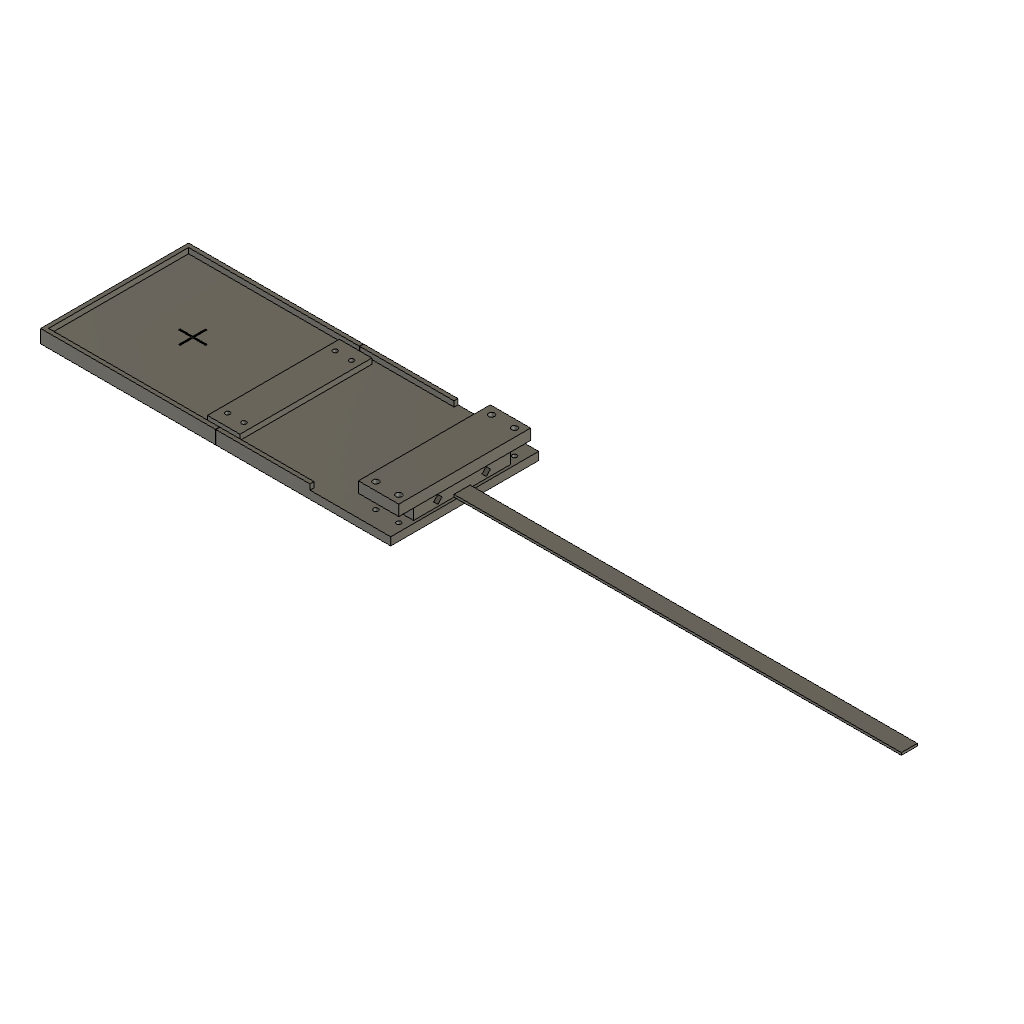
SkySafe_Weighted_Holder (Autodesk Fusion 360 design; units mm, degrees)
part number: 2026-10-11-03-14-07-749
part number: 2026-10-11-03-14-08-487
part number: 2026-10-11-03-14-09-230
part number: 2026-10-11-03-14-09-832
part number: 2026-10-11-03-14-10-188
part number: 2026-10-11-03-14-11-813
Autodesk Fusion 360 part; units mm, degrees
sketch "Flat root support floor sketch" plane through (0, 0, 0) normal (0, 0, 1) x (1, 0, 0) in component "01 Weighted root base - PRINT ONE"
  line L0 (-104, -55) -> (26, -55)
  line L1 (26, -55) -> (26, 55)
  line L2 (26, 55) -> (-104, 55)
  line L3 (-104, 55) -> (-104, -55)
extrude "Flat root support floor" add sketch "Flat root support floor sketch" along normal blind 6 makes body 1 in component "01 Weighted root base - PRINT ONE"
ref_plane "WorkPlane1" through (0, 0, 5.95) normal (0, 0, 1) x (1, 0, 0) in component "01 Weighted root base - PRINT ONE"
sketch "Front tray side lip -55 sketch" plane through (0, 0, 5.95) normal (0, 0, 1) x (1, 0, 0) in component "01 Weighted root base - PRINT ONE"
  line L0 (-104, -55) -> (-34, -55)
  line L1 (-34, -55) -> (-34, -52)
  line L2 (-34, -52) -> (-104, -52)
  line L3 (-104, -52) -> (-104, -55)
extrude "Front tray side lip -55" add sketch "Front tray side lip -55 sketch" along normal blind 4.05 bodies 1 in component "01 Weighted root base - PRINT ONE"
ref_plane "WorkPlane2" through (0, 0, 5.95) normal (0, 0, 1) x (1, 0, 0) in component "01 Weighted root base - PRINT ONE"
sketch "Front tray side lip 52 sketch" plane through (0, 0, 5.95) normal (0, 0, 1) x (1, 0, 0) in component "01 Weighted root base - PRINT ONE"
  line L0 (-104, 52) -> (-34, 52)
  line L1 (-34, 52) -> (-34, 55)
  line L2 (-34, 55) -> (-104, 55)
  line L3 (-104, 55) -> (-104, 52)
extrude "Front tray side lip 52" add sketch "Front tray side lip 52 sketch" along normal blind 4.05 bodies 1 in component "01 Weighted root base - PRINT ONE"
ref_plane "WorkPlane3" through (0, 0, 5.95) normal (0, 0, 1) x (1, 0, 0) in component "01 Weighted root base - PRINT ONE"
sketch "Original root locating pin -8" plane through (0, 0, 5.95) normal (0, 0, 1) x (1, 0, 0) in component "01 Weighted root base - PRINT ONE"
  circle A0 centre (8, -8) radius 1.5
extrude "Root locating pin -8" add sketch "Original root locating pin -8" along normal blind 2.05 bodies 1 in component "01 Weighted root base - PRINT ONE"
ref_plane "WorkPlane4" through (0, 0, 5.95) normal (0, 0, 1) x (1, 0, 0) in component "01 Weighted root base - PRINT ONE"
sketch "Original root locating pin 8" plane through (0, 0, 5.95) normal (0, 0, 1) x (1, 0, 0) in component "01 Weighted root base - PRINT ONE"
  circle A0 centre (8, 8) radius 1.5
extrude "Root locating pin 8" add sketch "Original root locating pin 8" along normal blind 2.05 bodies 1 in component "01 Weighted root base - PRINT ONE"
ref_plane "WorkPlane5" through (0, 0, -0.05) normal (0, 0, 1) x (1, 0, 0) in component "01 Weighted root base - PRINT ONE"
sketch "Root bolt (3, -43) clearance sketch" plane through (0, 0, -0.05) normal (0, 0, 1) x (1, 0, 0) in component "01 Weighted root base - PRINT ONE"
  circle A0 centre (3, -43) radius 1.7
  dimension "d25" = 3.4
  measures "d25" diameter of A0
extrude "Root bolt (3, -43) clearance" cut sketch "Root bolt (3, -43) clearance sketch" along normal blind 6.1 bodies 1 in component "01 Weighted root base - PRINT ONE"
ref_plane "WorkPlane6" through (0, 0, -0.05) normal (0, 0, 1) x (1, 0, 0) in component "01 Weighted root base - PRINT ONE"
sketch "Root bolt (3, -43) recessed head sketch" plane through (0, 0, -0.05) normal (0, 0, 1) x (1, 0, 0) in component "01 Weighted root base - PRINT ONE"
  circle A0 centre (3, -43) radius 3.2
  dimension "d30" = 6.4
  measures "d30" diameter of A0
extrude "Root bolt (3, -43) recessed head" cut sketch "Root bolt (3, -43) recessed head sketch" along normal blind 3.4 bodies 1 in component "01 Weighted root base - PRINT ONE"
ref_plane "WorkPlane7" through (0, 0, -0.05) normal (0, 0, 1) x (1, 0, 0) in component "01 Weighted root base - PRINT ONE"
sketch "Root bolt (3, 43) clearance sketch" plane through (0, 0, -0.05) normal (0, 0, 1) x (1, 0, 0) in component "01 Weighted root base - PRINT ONE"
  circle A0 centre (3, 43) radius 1.7
  dimension "d35" = 3.4
  measures "d35" diameter of A0
extrude "Root bolt (3, 43) clearance" cut sketch "Root bolt (3, 43) clearance sketch" along normal blind 6.1 bodies 1 in component "01 Weighted root base - PRINT ONE"
ref_plane "WorkPlane8" through (0, 0, -0.05) normal (0, 0, 1) x (1, 0, 0) in component "01 Weighted root base - PRINT ONE"
sketch "Root bolt (3, 43) recessed head sketch" plane through (0, 0, -0.05) normal (0, 0, 1) x (1, 0, 0) in component "01 Weighted root base - PRINT ONE"
  circle A0 centre (3, 43) radius 3.2
  dimension "d40" = 6.4
  measures "d40" diameter of A0
extrude "Root bolt (3, 43) recessed head" cut sketch "Root bolt (3, 43) recessed head sketch" along normal blind 3.4 bodies 1 in component "01 Weighted root base - PRINT ONE"
ref_plane "WorkPlane9" through (0, 0, -0.05) normal (0, 0, 1) x (1, 0, 0) in component "01 Weighted root base - PRINT ONE"
sketch "Root bolt (20, -43) clearance sketch" plane through (0, 0, -0.05) normal (0, 0, 1) x (1, 0, 0) in component "01 Weighted root base - PRINT ONE"
  circle A0 centre (20, -43) radius 1.7
  dimension "d45" = 3.4
  measures "d45" diameter of A0
extrude "Root bolt (20, -43) clearance" cut sketch "Root bolt (20, -43) clearance sketch" along normal blind 6.1 bodies 1 in component "01 Weighted root base - PRINT ONE"
ref_plane "WorkPlane10" through (0, 0, -0.05) normal (0, 0, 1) x (1, 0, 0) in component "01 Weighted root base - PRINT ONE"
sketch "Root bolt (20, -43) recessed head sketch" plane through (0, 0, -0.05) normal (0, 0, 1) x (1, 0, 0) in component "01 Weighted root base - PRINT ONE"
  circle A0 centre (20, -43) radius 3.2
  dimension "d50" = 6.4
  measures "d50" diameter of A0
extrude "Root bolt (20, -43) recessed head" cut sketch "Root bolt (20, -43) recessed head sketch" along normal blind 3.4 bodies 1 in component "01 Weighted root base - PRINT ONE"
ref_plane "WorkPlane11" through (0, 0, -0.05) normal (0, 0, 1) x (1, 0, 0) in component "01 Weighted root base - PRINT ONE"
sketch "Root bolt (20, 43) clearance sketch" plane through (0, 0, -0.05) normal (0, 0, 1) x (1, 0, 0) in component "01 Weighted root base - PRINT ONE"
  circle A0 centre (20, 43) radius 1.7
  dimension "d55" = 3.4
  measures "d55" diameter of A0
extrude "Root bolt (20, 43) clearance" cut sketch "Root bolt (20, 43) clearance sketch" along normal blind 6.1 bodies 1 in component "01 Weighted root base - PRINT ONE"
ref_plane "WorkPlane12" through (0, 0, -0.05) normal (0, 0, 1) x (1, 0, 0) in component "01 Weighted root base - PRINT ONE"
sketch "Root bolt (20, 43) recessed head sketch" plane through (0, 0, -0.05) normal (0, 0, 1) x (1, 0, 0) in component "01 Weighted root base - PRINT ONE"
  circle A0 centre (20, 43) radius 3.2
  dimension "d60" = 6.4
  measures "d60" diameter of A0
extrude "Root bolt (20, 43) recessed head" cut sketch "Root bolt (20, 43) recessed head sketch" along normal blind 3.4 bodies 1 in component "01 Weighted root base - PRINT ONE"
ref_plane "WorkPlane13" through (0, 0, -0.05) normal (0, 0, 1) x (1, 0, 0) in component "01 Weighted root base - PRINT ONE"
sketch "Tray joint front bolt -40 clearance sketch" plane through (0, 0, -0.05) normal (0, 0, 1) x (1, 0, 0) in component "01 Weighted root base - PRINT ONE"
  circle A0 centre (-98, -40) radius 1.7
  dimension "d65" = 3.4
  measures "d65" diameter of A0
extrude "Tray joint front bolt -40 clearance" cut sketch "Tray joint front bolt -40 clearance sketch" along normal blind 6.1 bodies 1 in component "01 Weighted root base - PRINT ONE"
ref_plane "WorkPlane14" through (0, 0, -0.05) normal (0, 0, 1) x (1, 0, 0) in component "01 Weighted root base - PRINT ONE"
sketch "Tray joint front bolt -40 recessed head sketch" plane through (0, 0, -0.05) normal (0, 0, 1) x (1, 0, 0) in component "01 Weighted root base - PRINT ONE"
  circle A0 centre (-98, -40) radius 3.2
  dimension "d70" = 6.4
  measures "d70" diameter of A0
extrude "Tray joint front bolt -40 recessed head" cut sketch "Tray joint front bolt -40 recessed head sketch" along normal blind 3.4 bodies 1 in component "01 Weighted root base - PRINT ONE"
ref_plane "WorkPlane15" through (0, 0, -0.05) normal (0, 0, 1) x (1, 0, 0) in component "01 Weighted root base - PRINT ONE"
sketch "Tray joint front bolt 40 clearance sketch" plane through (0, 0, -0.05) normal (0, 0, 1) x (1, 0, 0) in component "01 Weighted root base - PRINT ONE"
  circle A0 centre (-98, 40) radius 1.7
  dimension "d75" = 3.4
  measures "d75" diameter of A0
extrude "Tray joint front bolt 40 clearance" cut sketch "Tray joint front bolt 40 clearance sketch" along normal blind 6.1 bodies 1 in component "01 Weighted root base - PRINT ONE"
ref_plane "WorkPlane16" through (0, 0, -0.05) normal (0, 0, 1) x (1, 0, 0) in component "01 Weighted root base - PRINT ONE"
sketch "Tray joint front bolt 40 recessed head sketch" plane through (0, 0, -0.05) normal (0, 0, 1) x (1, 0, 0) in component "01 Weighted root base - PRINT ONE"
  circle A0 centre (-98, 40) radius 3.2
  dimension "d80" = 6.4
  measures "d80" diameter of A0
extrude "Tray joint front bolt 40 recessed head" cut sketch "Tray joint front bolt 40 recessed head sketch" along normal blind 3.4 bodies 1 in component "01 Weighted root base - PRINT ONE"
sketch "Rear tray floor sketch" plane through (0, 0, 0) normal (0, 0, 1) x (1, 0, 0) in component "02 Rear ballast tray - PRINT ONE"
  line L0 (-104, -55) -> (26, -55)
  line L1 (26, -55) -> (26, 55)
  line L2 (26, 55) -> (-104, 55)
  line L3 (-104, 55) -> (-104, -55)
extrude "Rear tray floor" add sketch "Rear tray floor sketch" along normal blind 6 separate body makes body 2 in component "02 Rear ballast tray - PRINT ONE"
ref_plane "WorkPlane1" through (0, 0, 5.95) normal (0, 0, 1) x (1, 0, 0) in component "02 Rear ballast tray - PRINT ONE"
sketch "Rear weight stop sketch" plane through (0, 0, 5.95) normal (0, 0, 1) x (1, 0, 0) in component "02 Rear ballast tray - PRINT ONE"
  line L0 (-104, -55) -> (-101, -55)
  line L1 (-101, -55) -> (-101, 55)
  line L2 (-101, 55) -> (-104, 55)
  line L3 (-104, 55) -> (-104, -55)
extrude "Rear weight stop" add sketch "Rear weight stop sketch" along normal blind 4.05 bodies 2 in component "02 Rear ballast tray - PRINT ONE"
ref_plane "WorkPlane2" through (0, 0, 5.95) normal (0, 0, 1) x (1, 0, 0) in component "02 Rear ballast tray - PRINT ONE"
sketch "Rear tray side lip -55 sketch" plane through (0, 0, 5.95) normal (0, 0, 1) x (1, 0, 0) in component "02 Rear ballast tray - PRINT ONE"
  line L0 (-104, -55) -> (26, -55)
  line L1 (26, -55) -> (26, -52)
  line L2 (26, -52) -> (-104, -52)
  line L3 (-104, -52) -> (-104, -55)
extrude "Rear tray side lip -55" add sketch "Rear tray side lip -55 sketch" along normal blind 4.05 bodies 2 in component "02 Rear ballast tray - PRINT ONE"
ref_plane "WorkPlane3" through (0, 0, 5.95) normal (0, 0, 1) x (1, 0, 0) in component "02 Rear ballast tray - PRINT ONE"
sketch "Rear tray side lip 52 sketch" plane through (0, 0, 5.95) normal (0, 0, 1) x (1, 0, 0) in component "02 Rear ballast tray - PRINT ONE"
  line L0 (-104, 52) -> (26, 52)
  line L1 (26, 52) -> (26, 55)
  line L2 (26, 55) -> (-104, 55)
  line L3 (-104, 55) -> (-104, 52)
extrude "Rear tray side lip 52" add sketch "Rear tray side lip 52 sketch" along normal blind 4.05 bodies 2 in component "02 Rear ballast tray - PRINT ONE"
ref_plane "WorkPlane4" through (0, 0, -0.05) normal (0, 0, 1) x (1, 0, 0) in component "02 Rear ballast tray - PRINT ONE"
sketch "Tray joint rear bolt -40 clearance sketch" plane through (0, 0, -0.05) normal (0, 0, 1) x (1, 0, 0) in component "02 Rear ballast tray - PRINT ONE"
  circle A0 centre (20, -40) radius 1.7
  dimension "d99" = 3.4
  measures "d99" diameter of A0
extrude "Tray joint rear bolt -40 clearance" cut sketch "Tray joint rear bolt -40 clearance sketch" along normal blind 6.1 bodies 2 in component "02 Rear ballast tray - PRINT ONE"
ref_plane "WorkPlane5" through (0, 0, -0.05) normal (0, 0, 1) x (1, 0, 0) in component "02 Rear ballast tray - PRINT ONE"
sketch "Tray joint rear bolt -40 recessed head sketch" plane through (0, 0, -0.05) normal (0, 0, 1) x (1, 0, 0) in component "02 Rear ballast tray - PRINT ONE"
  circle A0 centre (20, -40) radius 3.2
  dimension "d104" = 6.4
  measures "d104" diameter of A0
extrude "Tray joint rear bolt -40 recessed head" cut sketch "Tray joint rear bolt -40 recessed head sketch" along normal blind 3.4 bodies 2 in component "02 Rear ballast tray - PRINT ONE"
ref_plane "WorkPlane6" through (0, 0, -0.05) normal (0, 0, 1) x (1, 0, 0) in component "02 Rear ballast tray - PRINT ONE"
sketch "Tray joint rear bolt 40 clearance sketch" plane through (0, 0, -0.05) normal (0, 0, 1) x (1, 0, 0) in component "02 Rear ballast tray - PRINT ONE"
  circle A0 centre (20, 40) radius 1.7
  dimension "d109" = 3.4
  measures "d109" diameter of A0
extrude "Tray joint rear bolt 40 clearance" cut sketch "Tray joint rear bolt 40 clearance sketch" along normal blind 6.1 bodies 2 in component "02 Rear ballast tray - PRINT ONE"
ref_plane "WorkPlane7" through (0, 0, -0.05) normal (0, 0, 1) x (1, 0, 0) in component "02 Rear ballast tray - PRINT ONE"
sketch "Tray joint rear bolt 40 recessed head sketch" plane through (0, 0, -0.05) normal (0, 0, 1) x (1, 0, 0) in component "02 Rear ballast tray - PRINT ONE"
  circle A0 centre (20, 40) radius 3.2
  dimension "d114" = 6.4
  measures "d114" diameter of A0
extrude "Tray joint rear bolt 40 recessed head" cut sketch "Tray joint rear bolt 40 recessed head sketch" along normal blind 3.4 bodies 2 in component "02 Rear ballast tray - PRINT ONE"
ref_plane "WorkPlane8" through (0, 0, 5.6) normal (0, 0, 1) x (1, 0, 0) in component "02 Rear ballast tray - PRINT ONE"
sketch "Weight center line X sketch" plane through (0, 0, 5.6) normal (0, 0, 1) x (1, 0, 0) in component "02 Rear ballast tray - PRINT ONE"
  line L0 (-46.3, -10) -> (-45.3, -10)
  line L1 (-45.3, -10) -> (-45.3, 10)
  line L2 (-45.3, 10) -> (-46.3, 10)
  line L3 (-46.3, 10) -> (-46.3, -10)
extrude "Weight center line X" cut sketch "Weight center line X sketch" along normal blind 0.5 bodies 2 in component "02 Rear ballast tray - PRINT ONE"
ref_plane "WorkPlane9" through (0, 0, 5.6) normal (0, 0, 1) x (1, 0, 0) in component "02 Rear ballast tray - PRINT ONE"
sketch "Weight center line Y sketch" plane through (0, 0, 5.6) normal (0, 0, 1) x (1, 0, 0) in component "02 Rear ballast tray - PRINT ONE"
  line L0 (-55.8, -0.5) -> (-35.8, -0.5)
  line L1 (-35.8, -0.5) -> (-35.8, 0.5)
  line L2 (-35.8, 0.5) -> (-55.8, 0.5)
  line L3 (-55.8, 0.5) -> (-55.8, -0.5)
extrude "Weight center line Y" cut sketch "Weight center line Y sketch" along normal blind 0.5 bodies 2 in component "02 Rear ballast tray - PRINT ONE"
sketch "Wide upper splice sketch" plane through (0, 0, 0) normal (0, 0, 1) x (1, 0, 0) in component "03 Tray joint bridge - PRINT ONE"
  line L0 (0, -49) -> (24.2, -49)
  line L1 (24.2, -49) -> (24.2, 49)
  line L2 (24.2, 49) -> (0, 49)
  line L3 (0, 49) -> (0, -49)
extrude "Wide upper splice" add sketch "Wide upper splice sketch" along normal blind 4 separate body makes body 3 in component "03 Tray joint bridge - PRINT ONE"
ref_plane "WorkPlane1" through (0, 0, -0.05) normal (0, 0, 1) x (1, 0, 0) in component "03 Tray joint bridge - PRINT ONE"
sketch "Tray splice hole (6, -40) sketch" plane through (0, 0, -0.05) normal (0, 0, 1) x (1, 0, 0) in component "03 Tray joint bridge - PRINT ONE"
  circle A0 centre (6, -40) radius 1.7
  dimension "d129" = 3.4
  measures "d129" diameter of A0
extrude "Tray splice hole (6, -40)" cut sketch "Tray splice hole (6, -40) sketch" along normal blind 4.1 bodies 3 in component "03 Tray joint bridge - PRINT ONE"
ref_plane "WorkPlane2" through (0, 0, -0.05) normal (0, 0, 1) x (1, 0, 0) in component "03 Tray joint bridge - PRINT ONE"
sketch "Tray splice hole (6, 40) sketch" plane through (0, 0, -0.05) normal (0, 0, 1) x (1, 0, 0) in component "03 Tray joint bridge - PRINT ONE"
  circle A0 centre (6, 40) radius 1.7
  dimension "d134" = 3.4
  measures "d134" diameter of A0
extrude "Tray splice hole (6, 40)" cut sketch "Tray splice hole (6, 40) sketch" along normal blind 4.1 bodies 3 in component "03 Tray joint bridge - PRINT ONE"
ref_plane "WorkPlane3" through (0, 0, -0.05) normal (0, 0, 1) x (1, 0, 0) in component "03 Tray joint bridge - PRINT ONE"
sketch "Tray splice hole (18.2, -40) sketch" plane through (0, 0, -0.05) normal (0, 0, 1) x (1, 0, 0) in component "03 Tray joint bridge - PRINT ONE"
  circle A0 centre (18.2, -40) radius 1.7
  dimension "d139" = 3.4
  measures "d139" diameter of A0
extrude "Tray splice hole (18.2, -40)" cut sketch "Tray splice hole (18.2, -40) sketch" along normal blind 4.1 bodies 3 in component "03 Tray joint bridge - PRINT ONE"
ref_plane "WorkPlane4" through (0, 0, -0.05) normal (0, 0, 1) x (1, 0, 0) in component "03 Tray joint bridge - PRINT ONE"
sketch "Tray splice hole (18.2, 40) sketch" plane through (0, 0, -0.05) normal (0, 0, 1) x (1, 0, 0) in component "03 Tray joint bridge - PRINT ONE"
  circle A0 centre (18.2, 40) radius 1.7
  dimension "d144" = 3.4
  measures "d144" diameter of A0
extrude "Tray splice hole (18.2, 40)" cut sketch "Tray splice hole (18.2, 40) sketch" along normal blind 4.1 bodies 3 in component "03 Tray joint bridge - PRINT ONE"
sketch "Original upper root jaw sketch" plane through (0, 0, 0) normal (0, 0, 1) x (1, 0, 0) in component "04 Existing root cap - REUSE"
  line L0 (-4, -49) -> (26, -49)
  line L1 (26, -49) -> (26, 49)
  line L2 (26, 49) -> (-4, 49)
  line L3 (-4, 49) -> (-4, -49)
extrude "Original upper root jaw" add sketch "Original upper root jaw sketch" along normal blind 8 separate body makes body 4 in component "04 Existing root cap - REUSE"
ref_plane "WorkPlane1" through (0, 0, -0.05) normal (0, 0, 1) x (1, 0, 0) in component "04 Existing root cap - REUSE"
sketch "Original M4 clearance (3, -43) sketch" plane through (0, 0, -0.05) normal (0, 0, 1) x (1, 0, 0) in component "04 Existing root cap - REUSE"
  circle A0 centre (3, -43) radius 2.2
extrude "Original M4 clearance (3, -43)" cut sketch "Original M4 clearance (3, -43) sketch" along normal blind 8.1 bodies 4 in component "04 Existing root cap - REUSE"
ref_plane "WorkPlane2" through (0, 0, -0.05) normal (0, 0, 1) x (1, 0, 0) in component "04 Existing root cap - REUSE"
sketch "Original M4 clearance (3, 43) sketch" plane through (0, 0, -0.05) normal (0, 0, 1) x (1, 0, 0) in component "04 Existing root cap - REUSE"
  circle A0 centre (3, 43) radius 2.2
extrude "Original M4 clearance (3, 43)" cut sketch "Original M4 clearance (3, 43) sketch" along normal blind 8.1 bodies 4 in component "04 Existing root cap - REUSE"
ref_plane "WorkPlane3" through (0, 0, -0.05) normal (0, 0, 1) x (1, 0, 0) in component "04 Existing root cap - REUSE"
sketch "Original M4 clearance (20, -43) sketch" plane through (0, 0, -0.05) normal (0, 0, 1) x (1, 0, 0) in component "04 Existing root cap - REUSE"
  circle A0 centre (20, -43) radius 2.2
extrude "Original M4 clearance (20, -43)" cut sketch "Original M4 clearance (20, -43) sketch" along normal blind 8.1 bodies 4 in component "04 Existing root cap - REUSE"
ref_plane "WorkPlane4" through (0, 0, -0.05) normal (0, 0, 1) x (1, 0, 0) in component "04 Existing root cap - REUSE"
sketch "Original M4 clearance (20, 43) sketch" plane through (0, 0, -0.05) normal (0, 0, 1) x (1, 0, 0) in component "04 Existing root cap - REUSE"
  circle A0 centre (20, 43) radius 2.2
extrude "Original M4 clearance (20, 43)" cut sketch "Original M4 clearance (20, 43) sketch" along normal blind 8.1 bodies 4 in component "04 Existing root cap - REUSE"
ref_plane "WorkPlane1" through (0, 0, 6) normal (0, 0, 1) x (1, 0, 0) in component "REFERENCE ONLY - root tongue and unloaded wing span"
sketch "Existing root tongue envelope sketch" plane through (0, 0, 6) normal (0, 0, 1) x (1, 0, 0) in component "REFERENCE ONLY - root tongue and unloaded wing span"
  line L0 (0, -36) -> (24, -36)
  line L1 (24, -36) -> (24, 36)
  line L2 (24, 36) -> (0, 36)
  line L3 (0, 36) -> (0, -36)
extrude "Existing root tongue envelope" add sketch "Existing root tongue envelope sketch" along normal blind 10 separate body makes body 5 in component "REFERENCE ONLY - root tongue and unloaded wing span"
ref_plane "WorkPlane2" through (0, 0, 5.95) normal (0, 0, 1) x (1, 0, 0) in component "REFERENCE ONLY - root tongue and unloaded wing span"
sketch "Original pin socket -8 sketch" plane through (0, 0, 5.95) normal (0, 0, 1) x (1, 0, 0) in component "REFERENCE ONLY - root tongue and unloaded wing span"
  circle A0 centre (8, -8) radius 1.7
extrude "Original pin socket -8" cut sketch "Original pin socket -8 sketch" along normal blind 2.2 bodies 5 in component "REFERENCE ONLY - root tongue and unloaded wing span"
ref_plane "WorkPlane3" through (0, 0, 5.95) normal (0, 0, 1) x (1, 0, 0) in component "REFERENCE ONLY - root tongue and unloaded wing span"
sketch "Original pin socket 8 sketch" plane through (0, 0, 5.95) normal (0, 0, 1) x (1, 0, 0) in component "REFERENCE ONLY - root tongue and unloaded wing span"
  circle A0 centre (8, 8) radius 1.7
extrude "Original pin socket 8" cut sketch "Original pin socket 8 sketch" along normal blind 2.2 bodies 5 in component "REFERENCE ONLY - root tongue and unloaded wing span"
ref_plane "WorkPlane4" through (-0.05, 0, 0) normal (1, 0, 0) x (0, 1, 0) in component "REFERENCE ONLY - root tongue and unloaded wing span"
sketch "Root bamboo passage -18 sketch" plane through (-0.05, 0, 0) normal (1, 0, 0) x (0, 0, -1) in component "REFERENCE ONLY - root tongue and unloaded wing span"
  line L0 (-10.5, -21.182) -> (-7.318, -18)
  line L1 (-7.318, -18) -> (-10.5, -14.818)
  line L2 (-10.5, -14.818) -> (-13.682, -18)
  line L3 (-13.682, -18) -> (-10.5, -21.182)
extrude "Root bamboo passage -18" cut sketch "Root bamboo passage -18 sketch" along normal blind 24.1 bodies 5 in component "REFERENCE ONLY - root tongue and unloaded wing span"
ref_plane "WorkPlane5" through (-0.05, 0, 0) normal (1, 0, 0) x (0, 1, 0) in component "REFERENCE ONLY - root tongue and unloaded wing span"
sketch "Root bamboo passage 18 sketch" plane through (-0.05, 0, 0) normal (1, 0, 0) x (0, 0, -1) in component "REFERENCE ONLY - root tongue and unloaded wing span"
  line L0 (-10.5, 14.818) -> (-7.318, 18)
  line L1 (-7.318, 18) -> (-10.5, 21.182)
  line L2 (-10.5, 21.182) -> (-13.682, 18)
  line L3 (-13.682, 18) -> (-10.5, 14.818)
extrude "Root bamboo passage 18" cut sketch "Root bamboo passage 18 sketch" along normal blind 24.1 bodies 5 in component "REFERENCE ONLY - root tongue and unloaded wing span"
ref_plane "WorkPlane6" through (0, 0, 6) normal (0, 0, 1) x (1, 0, 0) in component "REFERENCE ONLY - root tongue and unloaded wing span"
sketch "Existing wing bending span envelope sketch" plane through (0, 0, 6) normal (0, 0, 1) x (1, 0, 0) in component "REFERENCE ONLY - root tongue and unloaded wing span"
  line L0 (24, -6) -> (356.4, -6)
  line L1 (356.4, -6) -> (356.4, 6)
  line L2 (356.4, 6) -> (24, 6)
  line L3 (24, 6) -> (24, -6)
extrude "Existing wing bending span envelope" add sketch "Existing wing bending span envelope sketch" along normal blind 1.8 bodies 5 in component "REFERENCE ONLY - root tongue and unloaded wing span"
component "02 Rear ballast tray - PRINT ONE" placed x (1, 0, 0) y (0, 1, 0) z (0, 0, 1) at (-130.2, 0, 0)
component "03 Tray joint bridge - PRINT ONE" placed x (1, 0, 0) y (0, 1, 0) z (0, 0, 1) at (-116.2, 0, 6)
component "04 Existing root cap - REUSE" placed x (1, 0, 0) y (0, 1, 0) z (0, 0, 1) at (0, 0, 16)
component "01 Weighted root base - PRINT ONE" placed x (1, 0, 0) y (0, 1, 0) z (0, 0, 1) at (0, 0, 0)
component "REFERENCE ONLY - root tongue and unloaded wing span" placed x (1, 0, 0) y (0, 1, 0) z (0, 0, 1) at (0, 0, 0)
equation "m3Clearance = 3.4 mm" comment "Weighted stand"
equation "m3HeadClearance = 6.4 mm" comment "Weighted stand"
equation "standFloor = 6 mm" comment "Weighted stand"
equation "bridgeThickness = 4 mm" comment "Weighted stand"
equation "d5 = standFloor"
equation "d25 = m3Clearance"
equation "d30 = m3HeadClearance"
equation "d35 = m3Clearance"
equation "d40 = m3HeadClearance"
equation "d45 = m3Clearance"
equation "d50 = m3HeadClearance"
equation "d55 = m3Clearance"
equation "d60 = m3HeadClearance"
equation "d65 = m3Clearance"
equation "d70 = m3HeadClearance"
equation "d75 = m3Clearance"
equation "d80 = m3HeadClearance"
equation "d83 = standFloor"
equation "d99 = m3Clearance"
equation "d104 = m3HeadClearance"
equation "d109 = m3Clearance"
equation "d114 = m3HeadClearance"
equation "d125 = bridgeThickness"
equation "d129 = m3Clearance"
equation "d134 = m3Clearance"
equation "d139 = m3Clearance"
equation "d144 = m3Clearance"
named bodies: "weighted_root_base native printable solid", "ballast_tray native printable solid", "tray_bridge native printable solid"
